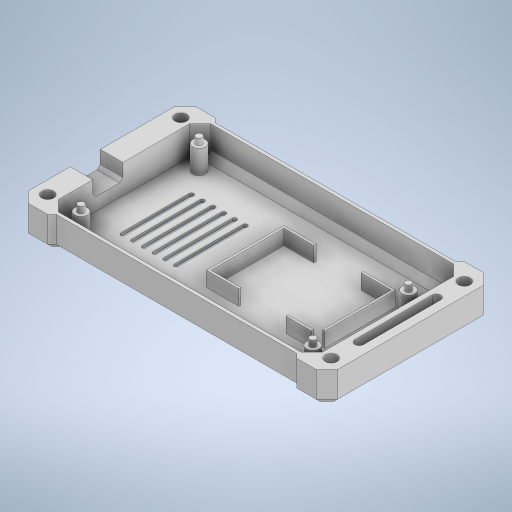
# Autodesk Inventor part: Coque V3
Saved by Autodesk Inventor 2024 (Build 280153000, 153)
## iProperties
Created: 2026-10-31
Part Number: Coque V3
Material: Générique
Document SubType Name: Modeling
Designer: berno
Density: 1 g/cm^3
Appearance: Par défaut
Mass: 39.06 g
Surface Area: 363.083 cm^2
Volume: 39.06 cm^3
Author: berno
Autodesk Inventor part; units mm, degrees
sketch "Esq Coque" plane through (0, 0, 0) normal (0, 1, 0) x (-1, 0, 0)
  line L0 (-72, -34) -> (-72, 34)
  line L1 (-72, 34) -> (-67, 39)
  line L2 (-67, 39) -> (-58, 39)
  line L3 (-58, 39) -> (-56, 37)
  line L4 (-56, 37) -> (56, 37)
  line L5 (56, 37) -> (58, 39)
  line L6 (58, 39) -> (67, 39)
  line L7 (67, 39) -> (72, 34)
  line L8 (72, 34) -> (72, -34)
  line L9 (72, -34) -> (67, -39)
  line L10 (67, -39) -> (58, -39)
  line L11 (58, -39) -> (56, -37)
  line L12 (56, -37) -> (-56, -37)
  line L13 (-56, -37) -> (-58, -39)
  line L14 (-58, -39) -> (-67, -39)
  line L15 (-67, -39) -> (-72, -34)
  constraints: 32 end point
extrude "Coque" add sketch "Esq Coque" along normal blind 15
chamfer "Chanfrein dos" distance 3 angle 45 16 edges at (69.5, 0, 36.5) (62.5, 0, 39) (57, 0, 38) (0, 0, 37) (-57, 0, 38) (-62.5, 0, 39) (-69.5, 0, 36.5) (-72, 0, 0) (-69.5, 0, -36.5) (-62.5, 0, -39) (-57, 0, -38) (0, 0, -37) (57, 0, -38) (62.5, 0, -39) (69.5, 0, -36.5) (72, 0, 0)
ref_plane "Plan de construction1" through (0, 15, 0) normal (0, 1, 0) x (-1, 0, 0)
sketch "Esq Cavite" plane through (0, 15, 0) normal (0, 1, 0) x (-1, 0, 0)
  line L0 (-61.5, -30.5) -> (-61.5, 30.5)
  line L1 (-61.5, 30.5) -> (-56.5, 35.5)
  line L2 (-56.5, 35.5) -> (56.5, 35.5)
  line L3 (56.5, 35.5) -> (61.5, 30.5)
  line L4 (61.5, 30.5) -> (61.5, -30.5)
  line L5 (61.5, -30.5) -> (56.5, -35.5)
  line L6 (56.5, -35.5) -> (-56.5, -35.5)
  line L7 (-56.5, -35.5) -> (-61.5, -30.5)
  constraints: 16 end point
extrude "Cavite" cut sketch "Esq Cavite" against normal blind 13.5
ref_plane "Plan de construction2" through (0, 1.5, 0) normal (0, 1, 0) x (-1, 0, 0)
sketch "Esq Logement batterie" plane through (0, 1.5, 0) normal (0, 1, 0) x (-1, 0, 0)
  line L0 (5, -18) -> (4, -18)
  line L1 (4, -18) -> (4, 18)
  line L2 (4, 18) -> (5, 18)
  line L3 (5, 18) -> (5, -18)
  line L4 (4, 17) -> (-10, 17)
  line L5 (-10, 17) -> (-10, 18)
  line L6 (-10, 18) -> (4, 18)
  line L7 (4, 18) -> (4, 17)
  line L8 (4, -18) -> (-10, -18)
  line L9 (-10, -18) -> (-10, -17)
  line L10 (-10, -17) -> (4, -17)
  line L11 (4, -17) -> (4, -18)
  line L12 (-32, 17) -> (-44, 17)
  line L13 (-44, 17) -> (-44, 18)
  line L14 (-44, 18) -> (-32, 18)
  line L15 (-32, 18) -> (-32, 17)
  line L16 (-32, -18) -> (-46, -18)
  line L17 (-46, -18) -> (-46, -17)
  line L18 (-46, -17) -> (-32, -17)
  line L19 (-32, -17) -> (-32, -18)
  line L20 (-46, -18) -> (-47, -18)
  line L21 (-47, -18) -> (-47, 15)
  line L22 (-47, 15) -> (-46, 15)
  line L23 (-46, 15) -> (-46, -18)
  constraints: 48 end point, 12 parallel, 6 horizontal, 6 perpendicular
extrude "Logement batterie" add sketch "Esq Logement batterie" along normal blind 7
ref_plane "Plan de construction3" through (0, 1.5, 0) normal (0, 1, 0) x (-1, 0, 0)
sketch "Esq Plots carte" plane through (0, 1.5, 0) normal (0, 1, 0) x (-1, 0, 0)
  circle A0 centre (-54, -17) radius 3
  circle A1 centre (54, -27.5) radius 3
  circle A2 centre (54, 27.5) radius 3
  circle A3 centre (-54, 27.5) radius 3
  constraints: 4 centre point
extrude "Plots carte" add sketch "Esq Plots carte" along normal blind 11
ref_plane "Plan de construction4" through (0, 12.5, 0) normal (0, 1, 0) x (-1, 0, 0)
sketch "Esq Pions carte" plane through (0, 12.5, 0) normal (0, 1, 0) x (-1, 0, 0)
  circle A0 centre (-54, -17) radius 1.5
  circle A1 centre (54, -27.5) radius 1.5
  circle A2 centre (54, 27.5) radius 1.5
  circle A3 centre (-54, 27.5) radius 1.5
  constraints: 4 centre point
extrude "Pions carte" add sketch "Esq Pions carte" along normal blind 3
ref_plane "Plan de construction5" through (0, 15, 0) normal (0, 1, 0) x (-1, 0, 0)
sketch "Esq Trous inserts M4" plane through (0, 15, 0) normal (0, 1, 0) x (-1, 0, 0)
  circle A0 centre (-66, 31) radius 2.8
  circle A1 centre (-66, -31) radius 2.8
  circle A2 centre (66, 31) radius 2.8
  circle A3 centre (66, -31) radius 2.8
  constraints: 4 centre point
extrude "Trous inserts M4" cut sketch "Esq Trous inserts M4" against normal blind 8.5
ref_plane "Plan de construction6" through (-72, 0, 0) normal (1, 0, 0) x (0, 1, 0)
sketch "Esq Tunnel USB-C" plane through (-72, 0, 0) normal (1, 0, 0) x (0, 1, 0)
  line L0 (15.5, 0.5) -> (9, 0.5)
  line L1 (9, 0.5) -> (7.5, 2)
  line L2 (7.5, 2) -> (7.5, 13)
  line L3 (7.5, 13) -> (9, 14.5)
  line L4 (9, 14.5) -> (15.5, 14.5)
  line L5 (15.5, 14.5) -> (15.5, 0.5)
  constraints: 12 end point
extrude "Tunnel USB-C" cut sketch "Esq Tunnel USB-C" along normal mid plane 22
sketch "Esq Passant dragonne" plane through (0, 0, 0) normal (0, 1, 0) x (-1, 0, 0)
  line L0 (-68, -18) -> (-68, 18)
  line L1 (-64, 18) -> (-64, -18)
  arc A0 (-64, 18) -> (-68, 18) centre (-66, 18) ccw
  arc A1 (-68, -18) -> (-64, -18) centre (-66, -18) ccw
  constraints: 4 end point, 4 point on circle, 2 centre point
extrude "Passant dragonne" cut sketch "Esq Passant dragonne" along normal blind 16
sketch "Esq Ventilation" plane through (0, 0, 0) normal (0, 1, 0) x (-1, 0, 0)
  line L0 (45, -16) -> (45, 16)
  line L1 (47, 16) -> (47, -16)
  arc A0 (47, 16) -> (45, 16) centre (46, 16) ccw
  arc A1 (45, -16) -> (47, -16) centre (46, -16) ccw
  line L2 (40, -16) -> (40, 16)
  line L3 (42, 16) -> (42, -16)
  arc A2 (42, 16) -> (40, 16) centre (41, 16) ccw
  arc A3 (40, -16) -> (42, -16) centre (41, -16) ccw
  line L4 (35, -16) -> (35, 16)
  line L5 (37, 16) -> (37, -16)
  arc A4 (37, 16) -> (35, 16) centre (36, 16) ccw
  arc A5 (35, -16) -> (37, -16) centre (36, -16) ccw
  line L6 (30, -16) -> (30, 16)
  line L7 (32, 16) -> (32, -16)
  arc A6 (32, 16) -> (30, 16) centre (31, 16) ccw
  arc A7 (30, -16) -> (32, -16) centre (31, -16) ccw
  line L8 (25, -16) -> (25, 16)
  line L9 (27, 16) -> (27, -16)
  arc A8 (27, 16) -> (25, 16) centre (26, 16) ccw
  arc A9 (25, -16) -> (27, -16) centre (26, -16) ccw
  line L10 (20, -16) -> (20, 16)
  line L11 (22, 16) -> (22, -16)
  arc A10 (22, 16) -> (20, 16) centre (21, 16) ccw
  arc A11 (20, -16) -> (22, -16) centre (21, -16) ccw
  constraints: 24 end point, 24 point on circle, 12 centre point
extrude "Ventilation" cut sketch "Esq Ventilation" along normal blind 2.5
sketch "Esq Renfort pied des murs" plane through (0, 0, 0) normal (1, 0, 0) x (0, 1, 0)
  line L0 (1.5, 32.5) -> (4.5, 35.5)
  line L1 (4.5, 35.5) -> (4.5, 36)
  line L2 (4.5, 36) -> (2, 36)
  line L3 (2, 36) -> (1, 35)
  line L4 (1, 35) -> (1, 32.5)
  line L5 (1, 32.5) -> (1.5, 32.5)
  line L6 (1.5, -32.5) -> (4.5, -35.5)
  line L7 (4.5, -35.5) -> (4.5, -36)
  line L8 (4.5, -36) -> (2, -36)
  line L9 (2, -36) -> (1, -35)
  line L10 (1, -35) -> (1, -32.5)
  line L11 (1, -32.5) -> (1.5, -32.5)
  constraints: 24 end point
extrude "Renfort pied des murs" add sketch "Esq Renfort pied des murs" along normal mid plane 113
